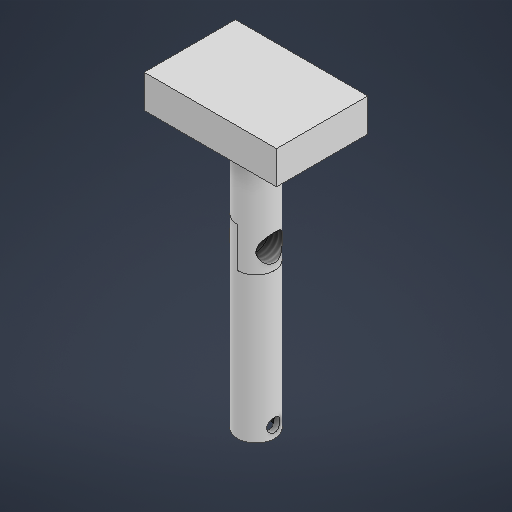
# Autodesk Inventor part: truc_khop_1
Saved by Autodesk Inventor 2026.2 (Build 302298000, 298)
## iProperties
Created: 2026-04-03
Part Number: truc_khop_1
Material: Generic
Document SubType Name: Modeling
Designer: thita
Density: 1 g/cm^3
Appearance: Default
Author: thita
Autodesk Inventor part; units mm, degrees
ref_plane "Work Plane1" through (-10, 40, -6.9) normal (0, 1, 0) x (0, 0, 1)
sketch "Sketch1" plane through (0, 0, 0) normal (0, 1, 0) x (-1, 0, 0)
  circle A0 centre (0, 0) radius 2.8
  dimension "d0" = 5.6
  constraints: 1 centre point, 1 coincident
  measures "d0" diameter of A0
extrude "Extrusion1" add sketch "Sketch1" along normal up to surface (40 mm away)
sketch "Sketch2" plane through (0, 40, 0) normal (0, 1, 0) x (1, 0, 0)
  line L0 (10, -6.9) -> (10, 6.9)
  line L1 (10, 6.9) -> (-10, 6.9)
  line L2 (-10, 6.9) -> (-10, -6.9)
  line L3 (-10, -6.9) -> (10, -6.9)
  line L4 (10, -6.9) -> (-10, 6.9) construction
  line L5 (10, 6.9) -> (-10, -6.9) construction
  point P0 (0, 0)
  dimension "d3" = 13.8
  dimension "d4" = 20
  constraints: 12 end point, 2 midpoint, 2 parallel, 1 perpendicular, 1 vertical
  measures "d3" distance of L0.start L0.end
  measures "d4" distance of L1.end L0.end
extrude "Extrusion2" add sketch "Sketch2" along normal blind 5
sketch "Sketch3" plane through (0, 0, 0) normal (0, -1, 0) x (1, 0, 0)
  circle A0 centre (0, 0) radius 2.8 projected
  circle A1 centre (0, 0) radius 2
  dimension "d7" = 4
  constraints: 1 centre point, 1 coincident
  measures "d7" diameter of A1
extrude "Extrusion3" cut sketch "Sketch3" against normal blind 3 contours A1
sketch "Sketch8" plane through (0, 0, 0) normal (0, 0, 1) x (1, 0, 0)
  line L0 (2.8, 0) -> (-2.8, 0) projected
  line L1 (2.8, 22) -> (0, 22)
  line L2 (0, 22) -> (0, 28)
  line L3 (0, 28) -> (-2.8, 28)
  point P0 (0, 0)
  dimension "d21" = 22
  dimension "d22" = 6
  dimension "d23" = 2.8
  constraints: 6 end point, 2 perpendicular
  measures "d21" distance of L0.start L1.start
  measures "d22" distance of L1.end L2.end
  measures "d23" distance of L2.end L3.end
split body "Split2" sketch "Sketch8" result two bodies curves L1 L2 L3 first body at (-0.5376, 9.3333, 2.2363)
sketch "Sketch9" plane through (0, 0, 0) normal (1, 0, 0) x (0, 1, 0)
  line L0 (28, 2.8) -> (22, 2.8) projected
  line L1 (22, -2.8) -> (28, -2.8) projected
  circle A0 centre (25, 0) radius 2
  point P0 (0, 0)
  dimension "d24" = 4
  constraints: 1 centre point
  measures "d24" diameter of A0
extrude "Extrusion5" cut sketch "Sketch9" along normal mid plane 10 bodies 3 2
thread "Thread2" size "M4x0.7" class "6H" standard "ISO Metric profile" length 12
thread "Thread3" size "M4x0.7" class "6H" standard "ISO Metric profile" length 12
sketch "Sketch10" plane through (10, 40, -6.9) normal (0, 0, -1) x (-1, 0, 0)
  line L0 (0, 5) -> (20, 5) projected
  line L1 (20, 0) -> (20, 5) projected
  line L2 (0, 5) -> (20, 5)
  line L3 (20, 5) -> (20, 0)
  line L4 (20, 0) -> (0, 0)
  line L5 (0, 0) -> (0, 5)
  point P0 (10, -40)
  constraints: 8 end point, 2 parallel, 1 horizontal, 1 perpendicular
ref_plane "Work Plane2" through (-40.0579, 32.5249, -7.7826) normal (0, 0, -1) x (0, 1, 0)
extrude "Extrusion6" add sketch "Sketch10" along normal up to surface (0.8826 mm away) bodies 3
sketch "Sketch11" plane through (10, 40, -7.7826) normal (0, 0, -1) x (-1, 0, 0)
  line L0 (0, 0) -> (0, 5) projected
  line L1 (20, 0) -> (0, 0) projected
  line L2 (20, 5) -> (20, 0) projected
  line L3 (0, 5) -> (20, 5) projected
  point P0 (10, -40)
ref_plane "Work Plane3" through (0, 40, -6.9) normal (0, 0, 1) x (1, 0, 0)
extrude "Extrusion7" cut sketch "Sketch11" against normal up to surface (0.8826 mm away) bodies 3
sketch "Sketch12" plane through (0, 0, 0) normal (1, 0, 0) x (0, 1, 0)
  circle A0 centre (1.7716, 0) radius 1
  point P0 (0, 0)
  dimension "d35" = 2
  constraints: 1 centre point
  measures "d35" diameter of A0
extrude "Extrusion8" cut sketch "Sketch12" along normal mid plane 20 bodies 2
body "Solid4"
body "Solid5"
